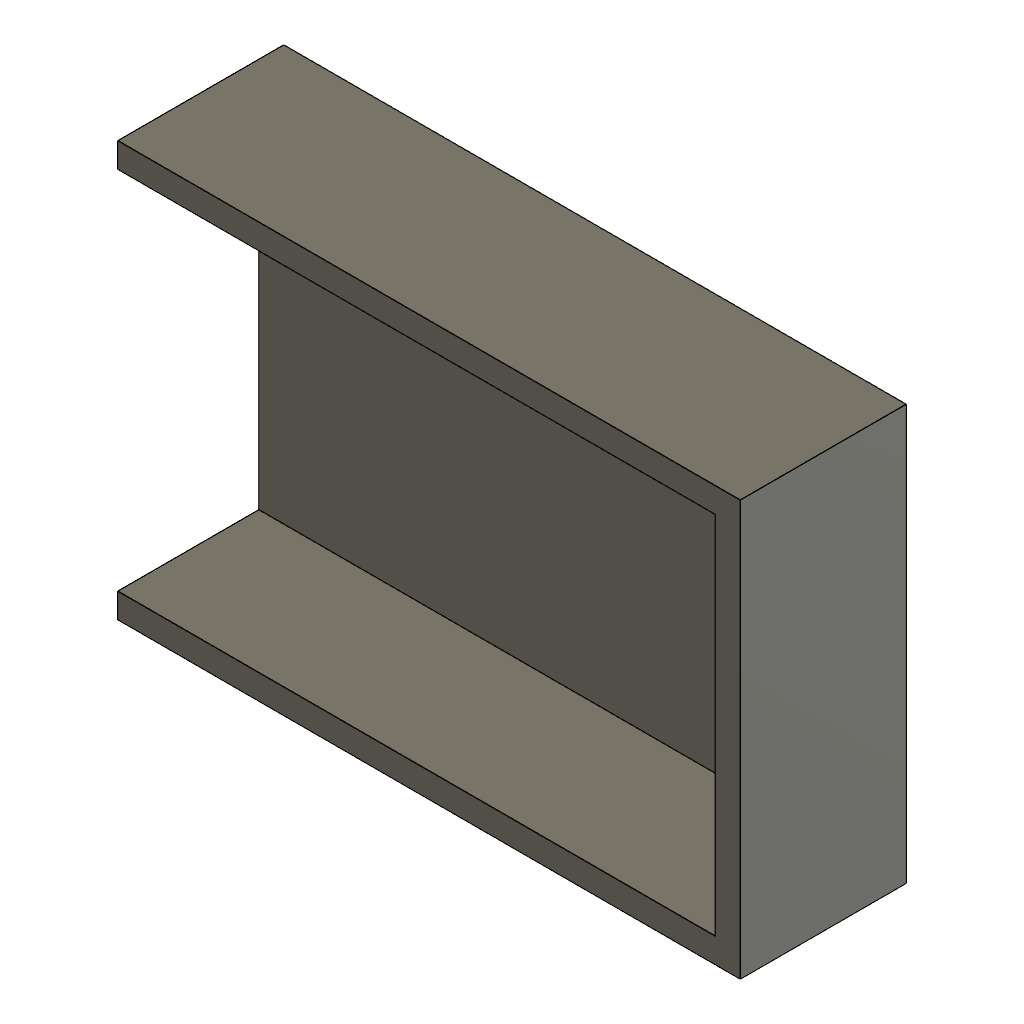
shell_two_faces (Autodesk Fusion 360 design; units mm, degrees)
part number: 2026-11-13-14-47-12-382
Autodesk Fusion 360 part; units mm, degrees
sketch "Sketch1" plane through (0, 0, 0) normal (0, 0, 1) x (1, 0, 0)
  line L0 (0, 0) -> (30, 0)
  line L1 (30, 0) -> (30, 20)
  line L2 (30, 20) -> (0, 20)
  line L3 (0, 20) -> (0, 0)
extrude "Extrude1" add sketch "Sketch1" along normal blind 8
shell "Shell1" thickness 1.2 removed faces 2 at (0, 13.3333, 5.3333) at (10, 13.3333, 8)
